Autodesk Fusion 360 part; units mm, degrees
(part 4 of 10)
ref_plane "WorkPlane1" through (0, 0, -5) normal (0, 0, 1) x (1, 0, 0) in component "METAL cap 01"
sketch "Visible cap sketch (2)" plane through (0, 0, -5) normal (0, 0, 1) x (1, 0, 0) in component "METAL cap 01"
  circle A0 centre (12, 120) radius 9
  dimension "d1404" = 12
  dimension "d1405" = 120
  dimension "d1406" = 18
  measures "d1404" horizontal distance of origin A0.centre
  measures "d1405" vertical distance of origin A0.centre
  measures "d1406" diameter of A0
extrude "Visible cap'" add sketch "Visible cap sketch (2)" along normal blind 5 separate body makes body 17 in component "METAL cap 01"
ref_plane "WorkPlane2" through (0, 0, -5) normal (0, 0, 1) x (1, 0, 0) in component "METAL cap 01"
sketch "M5 clearance sketch (2)" plane through (0, 0, -5) normal (0, 0, 1) x (1, 0, 0) in component "METAL cap 01"
  circle A0 centre (12, 120) radius 2.75
  dimension "d1411" = 12
  dimension "d1412" = 120
  dimension "d1413" = 5.5
  measures "d1411" horizontal distance of origin A0.centre
  measures "d1412" vertical distance of origin A0.centre
  measures "d1413" diameter of A0
extrude "M5 clearance'" cut sketch "M5 clearance sketch (2)" along normal blind 5 bodies 17 in component "METAL cap 01"
ref_plane "WorkPlane1" through (0, 0, 5) normal (0, 0, 1) x (1, 0, 0) in component "PRINT registration seat 01"
sketch "Rear bearing seat sketch (2)" plane through (0, 0, 5) normal (0, 0, 1) x (1, 0, 0) in component "PRINT registration seat 01"
  circle A0 centre (12, 120) radius 9
  dimension "d1418" = 12
  dimension "d1419" = 120
  dimension "d1420" = 18
  measures "d1418" horizontal distance of origin A0.centre
  measures "d1419" vertical distance of origin A0.centre
  measures "d1420" diameter of A0
extrude "Rear bearing seat'" add sketch "Rear bearing seat sketch (2)" along normal blind 2 separate body makes body 18 in component "PRINT registration seat 01"
ref_plane "WorkPlane2" through (0, 0, 5) normal (0, 0, 1) x (1, 0, 0) in component "PRINT registration seat 01"
sketch "Shoulder clearance sketch (2)" plane through (0, 0, 5) normal (0, 0, 1) x (1, 0, 0) in component "PRINT registration seat 01"
  circle A0 centre (12, 120) radius 4.2
  dimension "d1425" = 12
  dimension "d1426" = 120
  dimension "d1427" = 8.4
  measures "d1425" horizontal distance of origin A0.centre
  measures "d1426" vertical distance of origin A0.centre
  measures "d1427" diameter of A0
extrude "Shoulder clearance'" cut sketch "Shoulder clearance sketch (2)" along normal blind 2 bodies 18 in component "PRINT registration seat 01"
ref_plane "WorkPlane3" through (0, 0, 5) normal (0, 0, 1) x (1, 0, 0) in component "PRINT registration seat 01"
sketch "Forward registration peg sketch (4)" plane through (0, 0, 5) normal (0, 0, 1) x (1, 0, 0) in component "PRINT registration seat 01"
  circle A0 centre (7, 115) radius 1
  dimension "d1432" = 7
  dimension "d1433" = 115
  dimension "d1434" = 2
  measures "d1432" horizontal distance of origin A0.centre
  measures "d1433" vertical distance of origin A0.centre
  measures "d1434" diameter of A0
extrude "Forward registration peg'" add sketch "Forward registration peg sketch (4)" against normal blind 0.8 bodies 18 in component "PRINT registration seat 01"
ref_plane "WorkPlane4" through (0, 0, 5) normal (0, 0, 1) x (1, 0, 0) in component "PRINT registration seat 01"
sketch "Forward registration peg sketch (1) (2)" plane through (0, 0, 5) normal (0, 0, 1) x (1, 0, 0) in component "PRINT registration seat 01"
  circle A0 centre (7, 125) radius 1
  dimension "d1439" = 7
  dimension "d1440" = 125
  dimension "d1441" = 2
  measures "d1439" horizontal distance of origin A0.centre
  measures "d1440" vertical distance of origin A0.centre
  measures "d1441" diameter of A0
extrude "Forward registration peg (1)'" add sketch "Forward registration peg sketch (1) (2)" against normal blind 0.8 bodies 18 in component "PRINT registration seat 01"
ref_plane "WorkPlane5" through (0, 0, 5) normal (0, 0, 1) x (1, 0, 0) in component "PRINT registration seat 01"
sketch "Forward registration peg sketch (2) (2)" plane through (0, 0, 5) normal (0, 0, 1) x (1, 0, 0) in component "PRINT registration seat 01"
  circle A0 centre (17, 115) radius 1
  dimension "d1446" = 17
  dimension "d1447" = 115
  dimension "d1448" = 2
  measures "d1446" horizontal distance of origin A0.centre
  measures "d1447" vertical distance of origin A0.centre
  measures "d1448" diameter of A0
extrude "Forward registration peg (2)'" add sketch "Forward registration peg sketch (2) (2)" against normal blind 0.8 bodies 18 in component "PRINT registration seat 01"
ref_plane "WorkPlane6" through (0, 0, 5) normal (0, 0, 1) x (1, 0, 0) in component "PRINT registration seat 01"
sketch "Forward registration peg sketch (3) (2)" plane through (0, 0, 5) normal (0, 0, 1) x (1, 0, 0) in component "PRINT registration seat 01"
  circle A0 centre (17, 125) radius 1
  dimension "d1453" = 17
  dimension "d1454" = 125
  dimension "d1455" = 2
  measures "d1453" horizontal distance of origin A0.centre
  measures "d1454" vertical distance of origin A0.centre
  measures "d1455" diameter of A0
extrude "Forward registration peg (3)'" add sketch "Forward registration peg sketch (3) (2)" against normal blind 0.8 bodies 18 in component "PRINT registration seat 01"
sketch "8 mm shoulder sketch (2)" plane through (0, 0, 0) normal (0, 0, 1) x (1, 0, 0) in component "METAL stepped compression spacer 01"
  circle A0 centre (12, 120) radius 4
  dimension "d1458" = 12
  dimension "d1459" = 120
  dimension "d1460" = 8
  measures "d1458" horizontal distance of origin A0.centre
  measures "d1459" vertical distance of origin A0.centre
  measures "d1460" diameter of A0
extrude "8 mm shoulder'" add sketch "8 mm shoulder sketch (2)" along normal blind 7 separate body makes body 19 in component "METAL stepped compression spacer 01"
ref_plane "WorkPlane1" through (0, 0, 7) normal (0, 0, 1) x (1, 0, 0) in component "METAL stepped compression spacer 01"
sketch "12 mm base sketch (2)" plane through (0, 0, 7) normal (0, 0, 1) x (1, 0, 0) in component "METAL stepped compression spacer 01"
  circle A0 centre (12, 120) radius 6
  dimension "d1465" = 12
  dimension "d1466" = 120
  dimension "d1467" = 12
  measures "d1465" horizontal distance of origin A0.centre
  measures "d1466" vertical distance of origin A0.centre
  measures "d1467" diameter of A0
extrude "12 mm base'" add sketch "12 mm base sketch (2)" along normal blind 8 bodies 19 in component "METAL stepped compression spacer 01"
sketch "Through bore sketch (2)" plane through (0, 0, 0) normal (0, 0, 1) x (1, 0, 0) in component "METAL stepped compression spacer 01"
  circle A0 centre (12, 120) radius 2.75
  dimension "d1470" = 12
  dimension "d1471" = 120
  dimension "d1472" = 5.5
  measures "d1470" horizontal distance of origin A0.centre
  measures "d1471" vertical distance of origin A0.centre
  measures "d1472" diameter of A0
extrude "Through bore'" cut sketch "Through bore sketch (2)" along normal blind 15 bodies 19 in component "METAL stepped compression spacer 01"
ref_plane "WorkPlane1" through (0, 0, -8) normal (0, 0, 1) x (1, 0, 0) in component "REFERENCE front M5x25 01"
sketch "Button head envelope sketch (2)" plane through (0, 0, -8) normal (0, 0, 1) x (1, 0, 0) in component "REFERENCE front M5x25 01"
  circle A0 centre (12, 120) radius 4.75
  dimension "d1477" = 12
  dimension "d1478" = 120
  dimension "d1479" = 9.5
  measures "d1477" horizontal distance of origin A0.centre
  measures "d1478" vertical distance of origin A0.centre
  measures "d1479" diameter of A0
extrude "Button head envelope'" add sketch "Button head envelope sketch (2)" along normal blind 3 separate body makes body 20 in component "REFERENCE front M5x25 01"
ref_plane "WorkPlane2" through (0, 0, -5) normal (0, 0, 1) x (1, 0, 0) in component "REFERENCE front M5x25 01"
sketch "Shank envelope sketch (2)" plane through (0, 0, -5) normal (0, 0, 1) x (1, 0, 0) in component "REFERENCE front M5x25 01"
  circle A0 centre (12, 120) radius 2.5
  dimension "d1484" = 12
  dimension "d1485" = 120
  dimension "d1486" = 5
  measures "d1484" horizontal distance of origin A0.centre
  measures "d1485" vertical distance of origin A0.centre
  measures "d1486" diameter of A0
extrude "Shank envelope'" add sketch "Shank envelope sketch (2)" along normal blind 25 bodies 20 in component "REFERENCE front M5x25 01"
ref_plane "WorkPlane1" through (0, 0, 16.5) normal (0, 0, 1) x (1, 0, 0) in component "REFERENCE thin METAL channel nut front 01"
sketch "Thin nut envelope sketch (2)" plane through (0, 0, 16.5) normal (0, 0, 1) x (1, 0, 0) in component "REFERENCE thin METAL channel nut front 01"
  line L0 (7.6, 114) -> (16.4, 114)
  line L1 (16.4, 114) -> (16.4, 126)
  line L2 (16.4, 126) -> (7.6, 126)
  line L3 (7.6, 126) -> (7.6, 114)
  dimension "d1491" = 7.6
  dimension "d1492" = 114
  dimension "d1493" = 8.8
  dimension "d1494" = 12
  constraint horizontal L0
  constraint vertical L1
  constraint horizontal L2
  constraint vertical L3
  measures "d1491" horizontal distance of origin L0.start
  measures "d1492" vertical distance of origin L0.start
  measures "d1493" horizontal distance of L0.start L0.end
  measures "d1494" vertical distance of L0.end L1.end
extrude "Thin nut envelope'" add sketch "Thin nut envelope sketch (2)" along normal blind 2.7 separate body makes body 21 in component "REFERENCE thin METAL channel nut front 01"
ref_plane "WorkPlane2" through (0, 0, 16.5) normal (0, 0, 1) x (1, 0, 0) in component "REFERENCE thin METAL channel nut front 01"
sketch "Thread envelope sketch (2)" plane through (0, 0, 16.5) normal (0, 0, 1) x (1, 0, 0) in component "REFERENCE thin METAL channel nut front 01"
  circle A0 centre (12, 120) radius 2.6
  dimension "d1499" = 12
  dimension "d1500" = 120
  dimension "d1501" = 5.2
  measures "d1499" horizontal distance of origin A0.centre
  measures "d1500" vertical distance of origin A0.centre
  measures "d1501" diameter of A0
extrude "Thread envelope'" cut sketch "Thread envelope sketch (2)" along normal blind 2.7 bodies 21 in component "REFERENCE thin METAL channel nut front 01"
ref_plane "WorkPlane1" through (0, 0, -5) normal (0, 0, 1) x (1, 0, 0) in component "METAL cap 02"
sketch "Visible cap sketch (3)" plane through (0, 0, -5) normal (0, 0, 1) x (1, 0, 0) in component "METAL cap 02"
  circle A0 centre (12, 228) radius 9
  dimension "d1506" = 12
  dimension "d1507" = 228
  dimension "d1508" = 18
  measures "d1506" horizontal distance of origin A0.centre
  measures "d1507" vertical distance of origin A0.centre
  measures "d1508" diameter of A0
extrude "Visible cap''" add sketch "Visible cap sketch (3)" along normal blind 5 separate body makes body 22 in component "METAL cap 02"
ref_plane "WorkPlane2" through (0, 0, -5) normal (0, 0, 1) x (1, 0, 0) in component "METAL cap 02"
sketch "M5 clearance sketch (3)" plane through (0, 0, -5) normal (0, 0, 1) x (1, 0, 0) in component "METAL cap 02"
  circle A0 centre (12, 228) radius 2.75
  dimension "d1513" = 12
  dimension "d1514" = 228
  dimension "d1515" = 5.5
  measures "d1513" horizontal distance of origin A0.centre
  measures "d1514" vertical distance of origin A0.centre
  measures "d1515" diameter of A0
extrude "M5 clearance''" cut sketch "M5 clearance sketch (3)" along normal blind 5 bodies 22 in component "METAL cap 02"
ref_plane "WorkPlane1" through (0, 0, 5) normal (0, 0, 1) x (1, 0, 0) in component "PRINT registration seat 02"
sketch "Rear bearing seat sketch (3)" plane through (0, 0, 5) normal (0, 0, 1) x (1, 0, 0) in component "PRINT registration seat 02"
  circle A0 centre (12, 228) radius 9
  dimension "d1520" = 12
  dimension "d1521" = 228
  dimension "d1522" = 18
  measures "d1520" horizontal distance of origin A0.centre
  measures "d1521" vertical distance of origin A0.centre
  measures "d1522" diameter of A0
extrude "Rear bearing seat''" add sketch "Rear bearing seat sketch (3)" along normal blind 2 separate body makes body 23 in component "PRINT registration seat 02"
ref_plane "WorkPlane2" through (0, 0, 5) normal (0, 0, 1) x (1, 0, 0) in component "PRINT registration seat 02"
sketch "Shoulder clearance sketch (3)" plane through (0, 0, 5) normal (0, 0, 1) x (1, 0, 0) in component "PRINT registration seat 02"
  circle A0 centre (12, 228) radius 4.2
  dimension "d1527" = 12
  dimension "d1528" = 228
  dimension "d1529" = 8.4
  measures "d1527" horizontal distance of origin A0.centre
  measures "d1528" vertical distance of origin A0.centre
  measures "d1529" diameter of A0
extrude "Shoulder clearance''" cut sketch "Shoulder clearance sketch (3)" along normal blind 2 bodies 23 in component "PRINT registration seat 02"
ref_plane "WorkPlane3" through (0, 0, 5) normal (0, 0, 1) x (1, 0, 0) in component "PRINT registration seat 02"
sketch "Forward registration peg sketch (5)" plane through (0, 0, 5) normal (0, 0, 1) x (1, 0, 0) in component "PRINT registration seat 02"
  circle A0 centre (7, 223) radius 1
  dimension "d1534" = 7
  dimension "d1535" = 223
  dimension "d1536" = 2
  measures "d1534" horizontal distance of origin A0.centre
  measures "d1535" vertical distance of origin A0.centre
  measures "d1536" diameter of A0
extrude "Forward registration peg''" add sketch "Forward registration peg sketch (5)" against normal blind 0.8 bodies 23 in component "PRINT registration seat 02"
ref_plane "WorkPlane4" through (0, 0, 5) normal (0, 0, 1) x (1, 0, 0) in component "PRINT registration seat 02"
sketch "Forward registration peg sketch (1) (3)" plane through (0, 0, 5) normal (0, 0, 1) x (1, 0, 0) in component "PRINT registration seat 02"
  circle A0 centre (7, 233) radius 1
  dimension "d1541" = 7
  dimension "d1542" = 233
  dimension "d1543" = 2
  measures "d1541" horizontal distance of origin A0.centre
  measures "d1542" vertical distance of origin A0.centre
  measures "d1543" diameter of A0
extrude "Forward registration peg (1)''" add sketch "Forward registration peg sketch (1) (3)" against normal blind 0.8 bodies 23 in component "PRINT registration seat 02"
ref_plane "WorkPlane5" through (0, 0, 5) normal (0, 0, 1) x (1, 0, 0) in component "PRINT registration seat 02"
sketch "Forward registration peg sketch (2) (3)" plane through (0, 0, 5) normal (0, 0, 1) x (1, 0, 0) in component "PRINT registration seat 02"
  circle A0 centre (17, 223) radius 1
  dimension "d1548" = 17
  dimension "d1549" = 223
  dimension "d1550" = 2
  measures "d1548" horizontal distance of origin A0.centre
  measures "d1549" vertical distance of origin A0.centre
  measures "d1550" diameter of A0
extrude "Forward registration peg (2)''" add sketch "Forward registration peg sketch (2) (3)" against normal blind 0.8 bodies 23 in component "PRINT registration seat 02"
ref_plane "WorkPlane6" through (0, 0, 5) normal (0, 0, 1) x (1, 0, 0) in component "PRINT registration seat 02"
sketch "Forward registration peg sketch (3) (3)" plane through (0, 0, 5) normal (0, 0, 1) x (1, 0, 0) in component "PRINT registration seat 02"
  circle A0 centre (17, 233) radius 1
  dimension "d1555" = 17
  dimension "d1556" = 233
  dimension "d1557" = 2
  measures "d1555" horizontal distance of origin A0.centre
  measures "d1556" vertical distance of origin A0.centre
  measures "d1557" diameter of A0
extrude "Forward registration peg (3)''" add sketch "Forward registration peg sketch (3) (3)" against normal blind 0.8 bodies 23 in component "PRINT registration seat 02"
sketch "8 mm shoulder sketch (3)" plane through (0, 0, 0) normal (0, 0, 1) x (1, 0, 0) in component "METAL stepped compression spacer 02"
  circle A0 centre (12, 228) radius 4
  dimension "d1560" = 12
  dimension "d1561" = 228
  dimension "d1562" = 8
  measures "d1560" horizontal distance of origin A0.centre
  measures "d1561" vertical distance of origin A0.centre
  measures "d1562" diameter of A0
extrude "8 mm shoulder''" add sketch "8 mm shoulder sketch (3)" along normal blind 7 separate body makes body 24 in component "METAL stepped compression spacer 02"
ref_plane "WorkPlane1" through (0, 0, 7) normal (0, 0, 1) x (1, 0, 0) in component "METAL stepped compression spacer 02"
sketch "12 mm base sketch (3)" plane through (0, 0, 7) normal (0, 0, 1) x (1, 0, 0) in component "METAL stepped compression spacer 02"
  circle A0 centre (12, 228) radius 6
  dimension "d1567" = 12
  dimension "d1568" = 228
  dimension "d1569" = 12
  measures "d1567" horizontal distance of origin A0.centre
  measures "d1568" vertical distance of origin A0.centre
  measures "d1569" diameter of A0
extrude "12 mm base''" add sketch "12 mm base sketch (3)" along normal blind 8 bodies 24 in component "METAL stepped compression spacer 02"
sketch "Through bore sketch (3)" plane through (0, 0, 0) normal (0, 0, 1) x (1, 0, 0) in component "METAL stepped compression spacer 02"
  circle A0 centre (12, 228) radius 2.75
  dimension "d1572" = 12
  dimension "d1573" = 228
  dimension "d1574" = 5.5
  measures "d1572" horizontal distance of origin A0.centre
  measures "d1573" vertical distance of origin A0.centre
  measures "d1574" diameter of A0
extrude "Through bore''" cut sketch "Through bore sketch (3)" along normal blind 15 bodies 24 in component "METAL stepped compression spacer 02"
ref_plane "WorkPlane1" through (0, 0, -8) normal (0, 0, 1) x (1, 0, 0) in component "REFERENCE front M5x25 02"
sketch "Button head envelope sketch (3)" plane through (0, 0, -8) normal (0, 0, 1) x (1, 0, 0) in component "REFERENCE front M5x25 02"
  circle A0 centre (12, 228) radius 4.75
  dimension "d1579" = 12
  dimension "d1580" = 228
  dimension "d1581" = 9.5
  measures "d1579" horizontal distance of origin A0.centre
  measures "d1580" vertical distance of origin A0.centre
  measures "d1581" diameter of A0
extrude "Button head envelope''" add sketch "Button head envelope sketch (3)" along normal blind 3 separate body makes body 25 in component "REFERENCE front M5x25 02"
ref_plane "WorkPlane2" through (0, 0, -5) normal (0, 0, 1) x (1, 0, 0) in component "REFERENCE front M5x25 02"
sketch "Shank envelope sketch (3)" plane through (0, 0, -5) normal (0, 0, 1) x (1, 0, 0) in component "REFERENCE front M5x25 02"
  circle A0 centre (12, 228) radius 2.5
  dimension "d1586" = 12
  dimension "d1587" = 228
  dimension "d1588" = 5
  measures "d1586" horizontal distance of origin A0.centre
  measures "d1587" vertical distance of origin A0.centre
  measures "d1588" diameter of A0
extrude "Shank envelope''" add sketch "Shank envelope sketch (3)" along normal blind 25 bodies 25 in component "REFERENCE front M5x25 02"
ref_plane "WorkPlane1" through (0, 0, 16.5) normal (0, 0, 1) x (1, 0, 0) in component "REFERENCE thin METAL channel nut front 02"
sketch "Thin nut envelope sketch (3)" plane through (0, 0, 16.5) normal (0, 0, 1) x (1, 0, 0) in component "REFERENCE thin METAL channel nut front 02"
  line L0 (7.6, 222) -> (16.4, 222)
  line L1 (16.4, 222) -> (16.4, 234)
  line L2 (16.4, 234) -> (7.6, 234)
  line L3 (7.6, 234) -> (7.6, 222)
  dimension "d1593" = 7.6
  dimension "d1594" = 222
  dimension "d1595" = 8.8
  dimension "d1596" = 12
  constraint horizontal L0
  constraint vertical L1
  constraint horizontal L2
  constraint vertical L3
  measures "d1593" horizontal distance of origin L0.start
  measures "d1594" vertical distance of origin L0.start
  measures "d1595" horizontal distance of L0.start L0.end
  measures "d1596" vertical distance of L0.end L1.end
extrude "Thin nut envelope''" add sketch "Thin nut envelope sketch (3)" along normal blind 2.7 separate body makes body 26 in component "REFERENCE thin METAL channel nut front 02"
ref_plane "WorkPlane2" through (0, 0, 16.5) normal (0, 0, 1) x (1, 0, 0) in component "REFERENCE thin METAL channel nut front 02"
sketch "Thread envelope sketch (3)" plane through (0, 0, 16.5) normal (0, 0, 1) x (1, 0, 0) in component "REFERENCE thin METAL channel nut front 02"
  circle A0 centre (12, 228) radius 2.6
  dimension "d1601" = 12
  dimension "d1602" = 228
  dimension "d1603" = 5.2
  measures "d1601" horizontal distance of origin A0.centre
  measures "d1602" vertical distance of origin A0.centre
  measures "d1603" diameter of A0
extrude "Thread envelope''" cut sketch "Thread envelope sketch (3)" along normal blind 2.7 bodies 26 in component "REFERENCE thin METAL channel nut front 02"
ref_plane "WorkPlane1" through (0, 0, -5) normal (0, 0, 1) x (1, 0, 0) in component "METAL cap 10"
sketch "Visible cap sketch (4)" plane through (0, 0, -5) normal (0, 0, 1) x (1, 0, 0) in component "METAL cap 10"
  circle A0 centre (120, 12) radius 9
  dimension "d1608" = 120
  dimension "d1609" = 12
  dimension "d1610" = 18
  measures "d1608" horizontal distance of origin A0.centre
  measures "d1609" vertical distance of origin A0.centre
  measures "d1610" diameter of A0
extrude "Visible cap'''" add sketch "Visible cap sketch (4)" along normal blind 5 separate body makes body 27 in component "METAL cap 10"
ref_plane "WorkPlane2" through (0, 0, -5) normal (0, 0, 1) x (1, 0, 0) in component "METAL cap 10"
sketch "M5 clearance sketch (4)" plane through (0, 0, -5) normal (0, 0, 1) x (1, 0, 0) in component "METAL cap 10"
  circle A0 centre (120, 12) radius 2.75
  dimension "d1615" = 120
  dimension "d1616" = 12
  dimension "d1617" = 5.5
  measures "d1615" horizontal distance of origin A0.centre
  measures "d1616" vertical distance of origin A0.centre
  measures "d1617" diameter of A0
extrude "M5 clearance'''" cut sketch "M5 clearance sketch (4)" along normal blind 5 bodies 27 in component "METAL cap 10"
ref_plane "WorkPlane1" through (0, 0, 5) normal (0, 0, 1) x (1, 0, 0) in component "PRINT registration seat 10"
sketch "Rear bearing seat sketch (4)" plane through (0, 0, 5) normal (0, 0, 1) x (1, 0, 0) in component "PRINT registration seat 10"
  circle A0 centre (120, 12) radius 9
  dimension "d1622" = 120
  dimension "d1623" = 12
  dimension "d1624" = 18
  measures "d1622" horizontal distance of origin A0.centre
  measures "d1623" vertical distance of origin A0.centre
  measures "d1624" diameter of A0
extrude "Rear bearing seat'''" add sketch "Rear bearing seat sketch (4)" along normal blind 2 separate body makes body 28 in component "PRINT registration seat 10"
ref_plane "WorkPlane2" through (0, 0, 5) normal (0, 0, 1) x (1, 0, 0) in component "PRINT registration seat 10"
sketch "Shoulder clearance sketch (4)" plane through (0, 0, 5) normal (0, 0, 1) x (1, 0, 0) in component "PRINT registration seat 10"
  circle A0 centre (120, 12) radius 4.2
  dimension "d1629" = 120
  dimension "d1630" = 12
  dimension "d1631" = 8.4
  measures "d1629" horizontal distance of origin A0.centre
  measures "d1630" vertical distance of origin A0.centre
  measures "d1631" diameter of A0
extrude "Shoulder clearance'''" cut sketch "Shoulder clearance sketch (4)" along normal blind 2 bodies 28 in component "PRINT registration seat 10"
ref_plane "WorkPlane3" through (0, 0, 5) normal (0, 0, 1) x (1, 0, 0) in component "PRINT registration seat 10"
sketch "Forward registration peg sketch (6)" plane through (0, 0, 5) normal (0, 0, 1) x (1, 0, 0) in component "PRINT registration seat 10"
  circle A0 centre (115, 7) radius 1
  dimension "d1636" = 115
  dimension "d1637" = 7
  dimension "d1638" = 2
  measures "d1636" horizontal distance of origin A0.centre
  measures "d1637" vertical distance of origin A0.centre
  measures "d1638" diameter of A0
extrude "Forward registration peg'''" add sketch "Forward registration peg sketch (6)" against normal blind 0.8 bodies 28 in component "PRINT registration seat 10"
ref_plane "WorkPlane4" through (0, 0, 5) normal (0, 0, 1) x (1, 0, 0) in component "PRINT registration seat 10"
sketch "Forward registration peg sketch (1) (4)" plane through (0, 0, 5) normal (0, 0, 1) x (1, 0, 0) in component "PRINT registration seat 10"
  circle A0 centre (115, 17) radius 1
  dimension "d1643" = 115
  dimension "d1644" = 17
  dimension "d1645" = 2
  measures "d1643" horizontal distance of origin A0.centre
  measures "d1644" vertical distance of origin A0.centre
  measures "d1645" diameter of A0
extrude "Forward registration peg (1)'''" add sketch "Forward registration peg sketch (1) (4)" against normal blind 0.8 bodies 28 in component "PRINT registration seat 10"
ref_plane "WorkPlane5" through (0, 0, 5) normal (0, 0, 1) x (1, 0, 0) in component "PRINT registration seat 10"
sketch "Forward registration peg sketch (2) (4)" plane through (0, 0, 5) normal (0, 0, 1) x (1, 0, 0) in component "PRINT registration seat 10"
  circle A0 centre (125, 7) radius 1
  dimension "d1650" = 125
  dimension "d1651" = 7
  dimension "d1652" = 2
  measures "d1650" horizontal distance of origin A0.centre
  measures "d1651" vertical distance of origin A0.centre
  measures "d1652" diameter of A0
extrude "Forward registration peg (2)'''" add sketch "Forward registration peg sketch (2) (4)" against normal blind 0.8 bodies 28 in component "PRINT registration seat 10"
ref_plane "WorkPlane6" through (0, 0, 5) normal (0, 0, 1) x (1, 0, 0) in component "PRINT registration seat 10"
sketch "Forward registration peg sketch (3) (4)" plane through (0, 0, 5) normal (0, 0, 1) x (1, 0, 0) in component "PRINT registration seat 10"
  circle A0 centre (125, 17) radius 1
  dimension "d1657" = 125
  dimension "d1658" = 17
  dimension "d1659" = 2
  measures "d1657" horizontal distance of origin A0.centre
  measures "d1658" vertical distance of origin A0.centre
  measures "d1659" diameter of A0
extrude "Forward registration peg (3)'''" add sketch "Forward registration peg sketch (3) (4)" against normal blind 0.8 bodies 28 in component "PRINT registration seat 10"
sketch "8 mm shoulder sketch (4)" plane through (0, 0, 0) normal (0, 0, 1) x (1, 0, 0) in component "METAL stepped compression spacer 10"
  circle A0 centre (120, 12) radius 4
  dimension "d1662" = 120
  dimension "d1663" = 12
  dimension "d1664" = 8
  measures "d1662" horizontal distance of origin A0.centre
  measures "d1663" vertical distance of origin A0.centre
  measures "d1664" diameter of A0
extrude "8 mm shoulder'''" add sketch "8 mm shoulder sketch (4)" along normal blind 7 separate body makes body 29 in component "METAL stepped compression spacer 10"
ref_plane "WorkPlane1" through (0, 0, 7) normal (0, 0, 1) x (1, 0, 0) in component "METAL stepped compression spacer 10"
sketch "12 mm base sketch (4)" plane through (0, 0, 7) normal (0, 0, 1) x (1, 0, 0) in component "METAL stepped compression spacer 10"
  circle A0 centre (120, 12) radius 6
  dimension "d1669" = 120
  dimension "d1670" = 12
  dimension "d1671" = 12
  measures "d1669" horizontal distance of origin A0.centre
  measures "d1670" vertical distance of origin A0.centre
  measures "d1671" diameter of A0
extrude "12 mm base'''" add sketch "12 mm base sketch (4)" along normal blind 8 bodies 29 in component "METAL stepped compression spacer 10"
sketch "Through bore sketch (4)" plane through (0, 0, 0) normal (0, 0, 1) x (1, 0, 0) in component "METAL stepped compression spacer 10"
  circle A0 centre (120, 12) radius 2.75
  dimension "d1674" = 120
  dimension "d1675" = 12
  dimension "d1676" = 5.5
  measures "d1674" horizontal distance of origin A0.centre
  measures "d1675" vertical distance of origin A0.centre
  measures "d1676" diameter of A0
extrude "Through bore'''" cut sketch "Through bore sketch (4)" along normal blind 15 bodies 29 in component "METAL stepped compression spacer 10"
ref_plane "WorkPlane1" through (0, 0, -8) normal (0, 0, 1) x (1, 0, 0) in component "REFERENCE front M5x25 10"
sketch "Button head envelope sketch (4)" plane through (0, 0, -8) normal (0, 0, 1) x (1, 0, 0) in component "REFERENCE front M5x25 10"
  circle A0 centre (120, 12) radius 4.75
  dimension "d1681" = 120
  dimension "d1682" = 12
  dimension "d1683" = 9.5
  measures "d1681" horizontal distance of origin A0.centre
  measures "d1682" vertical distance of origin A0.centre
  measures "d1683" diameter of A0
extrude "Button head envelope'''" add sketch "Button head envelope sketch (4)" along normal blind 3 separate body makes body 30 in component "REFERENCE front M5x25 10"
ref_plane "WorkPlane2" through (0, 0, -5) normal (0, 0, 1) x (1, 0, 0) in component "REFERENCE front M5x25 10"
sketch "Shank envelope sketch (4)" plane through (0, 0, -5) normal (0, 0, 1) x (1, 0, 0) in component "REFERENCE front M5x25 10"
  circle A0 centre (120, 12) radius 2.5
  dimension "d1688" = 120
  dimension "d1689" = 12
  dimension "d1690" = 5
  measures "d1688" horizontal distance of origin A0.centre
  measures "d1689" vertical distance of origin A0.centre
  measures "d1690" diameter of A0
extrude "Shank envelope'''" add sketch "Shank envelope sketch (4)" along normal blind 25 bodies 30 in component "REFERENCE front M5x25 10"
ref_plane "WorkPlane1" through (0, 0, 16.5) normal (0, 0, 1) x (1, 0, 0) in component "REFERENCE thin METAL channel nut front 10"
sketch "Thin nut envelope sketch (4)" plane through (0, 0, 16.5) normal (0, 0, 1) x (1, 0, 0) in component "REFERENCE thin METAL channel nut front 10"
  line L0 (115.6, 6) -> (124.4, 6)
  line L1 (124.4, 6) -> (124.4, 18)
  line L2 (124.4, 18) -> (115.6, 18)
  line L3 (115.6, 18) -> (115.6, 6)
  dimension "d1695" = 115.6
  dimension "d1696" = 6
  dimension "d1697" = 8.8
  dimension "d1698" = 12
  constraint horizontal L0
  constraint vertical L1
  constraint horizontal L2
  constraint vertical L3
  measures "d1695" horizontal distance of origin L0.start
  measures "d1696" vertical distance of origin L0.start
  measures "d1697" horizontal distance of L0.start L0.end
  measures "d1698" vertical distance of L0.end L1.end
extrude "Thin nut envelope'''" add sketch "Thin nut envelope sketch (4)" along normal blind 2.7 separate body makes body 31 in component "REFERENCE thin METAL channel nut front 10"
ref_plane "WorkPlane2" through (0, 0, 16.5) normal (0, 0, 1) x (1, 0, 0) in component "REFERENCE thin METAL channel nut front 10"
sketch "Thread envelope sketch (4)" plane through (0, 0, 16.5) normal (0, 0, 1) x (1, 0, 0) in component "REFERENCE thin METAL channel nut front 10"
  circle A0 centre (120, 12) radius 2.6
  dimension "d1703" = 120
  dimension "d1704" = 12
  dimension "d1705" = 5.2
  measures "d1703" horizontal distance of origin A0.centre
  measures "d1704" vertical distance of origin A0.centre
  measures "d1705" diameter of A0
extrude "Thread envelope'''" cut sketch "Thread envelope sketch (4)" along normal blind 2.7 bodies 31 in component "REFERENCE thin METAL channel nut front 10"
ref_plane "WorkPlane1" through (0, 0, -5) normal (0, 0, 1) x (1, 0, 0) in component "METAL cap 11"
sketch "Visible cap sketch (5)" plane through (0, 0, -5) normal (0, 0, 1) x (1, 0, 0) in component "METAL cap 11"
  circle A0 centre (120, 120) radius 9
  dimension "d1710" = 120
  dimension "d1711" = 120
  dimension "d1712" = 18
  measures "d1710" horizontal distance of origin A0.centre
  measures "d1711" vertical distance of origin A0.centre
  measures "d1712" diameter of A0
extrude "Visible cap''''" add sketch "Visible cap sketch (5)" along normal blind 5 separate body makes body 32 in component "METAL cap 11"
ref_plane "WorkPlane2" through (0, 0, -5) normal (0, 0, 1) x (1, 0, 0) in component "METAL cap 11"
sketch "M5 clearance sketch (5)" plane through (0, 0, -5) normal (0, 0, 1) x (1, 0, 0) in component "METAL cap 11"
  circle A0 centre (120, 120) radius 2.75
  dimension "d1717" = 120
  dimension "d1718" = 120
  dimension "d1719" = 5.5
  measures "d1717" horizontal distance of origin A0.centre
  measures "d1718" vertical distance of origin A0.centre
  measures "d1719" diameter of A0
extrude "M5 clearance''''" cut sketch "M5 clearance sketch (5)" along normal blind 5 bodies 32 in component "METAL cap 11"
ref_plane "WorkPlane1" through (0, 0, 5) normal (0, 0, 1) x (1, 0, 0) in component "PRINT registration seat 11"
sketch "Rear bearing seat sketch (5)" plane through (0, 0, 5) normal (0, 0, 1) x (1, 0, 0) in component "PRINT registration seat 11"
  circle A0 centre (120, 120) radius 9
  dimension "d1724" = 120
  dimension "d1725" = 120
  dimension "d1726" = 18
  measures "d1724" horizontal distance of origin A0.centre
  measures "d1725" vertical distance of origin A0.centre
  measures "d1726" diameter of A0
extrude "Rear bearing seat''''" add sketch "Rear bearing seat sketch (5)" along normal blind 2 separate body makes body 33 in component "PRINT registration seat 11"
ref_plane "WorkPlane2" through (0, 0, 5) normal (0, 0, 1) x (1, 0, 0) in component "PRINT registration seat 11"
sketch "Shoulder clearance sketch (5)" plane through (0, 0, 5) normal (0, 0, 1) x (1, 0, 0) in component "PRINT registration seat 11"
  circle A0 centre (120, 120) radius 4.2
  dimension "d1731" = 120
  dimension "d1732" = 120
  dimension "d1733" = 8.4
  measures "d1731" horizontal distance of origin A0.centre
  measures "d1732" vertical distance of origin A0.centre
  measures "d1733" diameter of A0
extrude "Shoulder clearance''''" cut sketch "Shoulder clearance sketch (5)" along normal blind 2 bodies 33 in component "PRINT registration seat 11"
ref_plane "WorkPlane3" through (0, 0, 5) normal (0, 0, 1) x (1, 0, 0) in component "PRINT registration seat 11"
sketch "Forward registration peg sketch (7)" plane through (0, 0, 5) normal (0, 0, 1) x (1, 0, 0) in component "PRINT registration seat 11"
  circle A0 centre (115, 115) radius 1
  dimension "d1738" = 115
  dimension "d1739" = 115
  dimension "d1740" = 2
  measures "d1738" horizontal distance of origin A0.centre
  measures "d1739" vertical distance of origin A0.centre
  measures "d1740" diameter of A0
extrude "Forward registration peg''''" add sketch "Forward registration peg sketch (7)" against normal blind 0.8 bodies 33 in component "PRINT registration seat 11"
ref_plane "WorkPlane4" through (0, 0, 5) normal (0, 0, 1) x (1, 0, 0) in component "PRINT registration seat 11"
sketch "Forward registration peg sketch (1) (5)" plane through (0, 0, 5) normal (0, 0, 1) x (1, 0, 0) in component "PRINT registration seat 11"
  circle A0 centre (115, 125) radius 1
  dimension "d1745" = 115
  dimension "d1746" = 125
  dimension "d1747" = 2
  measures "d1745" horizontal distance of origin A0.centre
  measures "d1746" vertical distance of origin A0.centre
  measures "d1747" diameter of A0
extrude "Forward registration peg (1)''''" add sketch "Forward registration peg sketch (1) (5)" against normal blind 0.8 bodies 33 in component "PRINT registration seat 11"
ref_plane "WorkPlane5" through (0, 0, 5) normal (0, 0, 1) x (1, 0, 0) in component "PRINT registration seat 11"
sketch "Forward registration peg sketch (2) (5)" plane through (0, 0, 5) normal (0, 0, 1) x (1, 0, 0) in component "PRINT registration seat 11"
  circle A0 centre (125, 115) radius 1
  dimension "d1752" = 125
  dimension "d1753" = 115
  dimension "d1754" = 2
  measures "d1752" horizontal distance of origin A0.centre
  measures "d1753" vertical distance of origin A0.centre
  measures "d1754" diameter of A0
extrude "Forward registration peg (2)''''" add sketch "Forward registration peg sketch (2) (5)" against normal blind 0.8 bodies 33 in component "PRINT registration seat 11"
ref_plane "WorkPlane6" through (0, 0, 5) normal (0, 0, 1) x (1, 0, 0) in component "PRINT registration seat 11"
sketch "Forward registration peg sketch (3) (5)" plane through (0, 0, 5) normal (0, 0, 1) x (1, 0, 0) in component "PRINT registration seat 11"
  circle A0 centre (125, 125) radius 1
  dimension "d1759" = 125
  dimension "d1760" = 125
  dimension "d1761" = 2
  measures "d1759" horizontal distance of origin A0.centre
  measures "d1760" vertical distance of origin A0.centre
  measures "d1761" diameter of A0
extrude "Forward registration peg (3)''''" add sketch "Forward registration peg sketch (3) (5)" against normal blind 0.8 bodies 33 in component "PRINT registration seat 11"
sketch "8 mm shoulder sketch (5)" plane through (0, 0, 0) normal (0, 0, 1) x (1, 0, 0) in component "METAL stepped compression spacer 11"
  circle A0 centre (120, 120) radius 4
  dimension "d1764" = 120
  dimension "d1765" = 120
  dimension "d1766" = 8
  measures "d1764" horizontal distance of origin A0.centre
  measures "d1765" vertical distance of origin A0.centre
  measures "d1766" diameter of A0
extrude "8 mm shoulder''''" add sketch "8 mm shoulder sketch (5)" along normal blind 7 separate body makes body 34 in component "METAL stepped compression spacer 11"
ref_plane "WorkPlane1" through (0, 0, 7) normal (0, 0, 1) x (1, 0, 0) in component "METAL stepped compression spacer 11"
sketch "12 mm base sketch (5)" plane through (0, 0, 7) normal (0, 0, 1) x (1, 0, 0) in component "METAL stepped compression spacer 11"
  circle A0 centre (120, 120) radius 6
  dimension "d1771" = 120
  dimension "d1772" = 120
  dimension "d1773" = 12
  measures "d1771" horizontal distance of origin A0.centre
  measures "d1772" vertical distance of origin A0.centre
  measures "d1773" diameter of A0
extrude "12 mm base''''" add sketch "12 mm base sketch (5)" along normal blind 8 bodies 34 in component "METAL stepped compression spacer 11"
sketch "Through bore sketch (5)" plane through (0, 0, 0) normal (0, 0, 1) x (1, 0, 0) in component "METAL stepped compression spacer 11"
  circle A0 centre (120, 120) radius 2.75
  dimension "d1776" = 120
  dimension "d1777" = 120
  dimension "d1778" = 5.5
  measures "d1776" horizontal distance of origin A0.centre
  measures "d1777" vertical distance of origin A0.centre
  measures "d1778" diameter of A0
extrude "Through bore''''" cut sketch "Through bore sketch (5)" along normal blind 15 bodies 34 in component "METAL stepped compression spacer 11"
ref_plane "WorkPlane1" through (0, 0, -8) normal (0, 0, 1) x (1, 0, 0) in component "REFERENCE front M5x25 11"
sketch "Button head envelope sketch (5)" plane through (0, 0, -8) normal (0, 0, 1) x (1, 0, 0) in component "REFERENCE front M5x25 11"
  circle A0 centre (120, 120) radius 4.75
  dimension "d1783" = 120
  dimension "d1784" = 120
  dimension "d1785" = 9.5
  measures "d1783" horizontal distance of origin A0.centre
  measures "d1784" vertical distance of origin A0.centre
  measures "d1785" diameter of A0
extrude "Button head envelope''''" add sketch "Button head envelope sketch (5)" along normal blind 3 separate body makes body 35 in component "REFERENCE front M5x25 11"
ref_plane "WorkPlane2" through (0, 0, -5) normal (0, 0, 1) x (1, 0, 0) in component "REFERENCE front M5x25 11"
sketch "Shank envelope sketch (5)" plane through (0, 0, -5) normal (0, 0, 1) x (1, 0, 0) in component "REFERENCE front M5x25 11"
  circle A0 centre (120, 120) radius 2.5
  dimension "d1790" = 120
  dimension "d1791" = 120
  dimension "d1792" = 5
  measures "d1790" horizontal distance of origin A0.centre
  measures "d1791" vertical distance of origin A0.centre
  measures "d1792" diameter of A0
extrude "Shank envelope''''" add sketch "Shank envelope sketch (5)" along normal blind 25 bodies 35 in component "REFERENCE front M5x25 11"
ref_plane "WorkPlane1" through (0, 0, 16.5) normal (0, 0, 1) x (1, 0, 0) in component "REFERENCE thin METAL channel nut front 11"
sketch "Thin nut envelope sketch (5)" plane through (0, 0, 16.5) normal (0, 0, 1) x (1, 0, 0) in component "REFERENCE thin METAL channel nut front 11"
  line L0 (115.6, 114) -> (124.4, 114)
  line L1 (124.4, 114) -> (124.4, 126)
  line L2 (124.4, 126) -> (115.6, 126)
  line L3 (115.6, 126) -> (115.6, 114)
  dimension "d1797" = 115.6
  dimension "d1798" = 114
  dimension "d1799" = 8.8
  dimension "d1800" = 12
  constraint horizontal L0
  constraint vertical L1
  constraint horizontal L2
  constraint vertical L3
  measures "d1797" horizontal distance of origin L0.start
  measures "d1798" vertical distance of origin L0.start
  measures "d1799" horizontal distance of L0.start L0.end
  measures "d1800" vertical distance of L0.end L1.end
extrude "Thin nut envelope''''" add sketch "Thin nut envelope sketch (5)" along normal blind 2.7 separate body makes body 36 in component "REFERENCE thin METAL channel nut front 11"
ref_plane "WorkPlane2" through (0, 0, 16.5) normal (0, 0, 1) x (1, 0, 0) in component "REFERENCE thin METAL channel nut front 11"
sketch "Thread envelope sketch (5)" plane through (0, 0, 16.5) normal (0, 0, 1) x (1, 0, 0) in component "REFERENCE thin METAL channel nut front 11"
  circle A0 centre (120, 120) radius 2.6
  dimension "d1805" = 120
  dimension "d1806" = 120
  dimension "d1807" = 5.2
  measures "d1805" horizontal distance of origin A0.centre
  measures "d1806" vertical distance of origin A0.centre
  measures "d1807" diameter of A0
extrude "Thread envelope''''" cut sketch "Thread envelope sketch (5)" along normal blind 2.7 bodies 36 in component "REFERENCE thin METAL channel nut front 11"
ref_plane "WorkPlane1" through (0, 0, -5) normal (0, 0, 1) x (1, 0, 0) in component "METAL cap 12"
sketch "Visible cap sketch (6)" plane through (0, 0, -5) normal (0, 0, 1) x (1, 0, 0) in component "METAL cap 12"
  circle A0 centre (120, 228) radius 9
  dimension "d1812" = 120
  dimension "d1813" = 228
  dimension "d1814" = 18
  measures "d1812" horizontal distance of origin A0.centre
  measures "d1813" vertical distance of origin A0.centre
  measures "d1814" diameter of A0
extrude "Visible cap'''''" add sketch "Visible cap sketch (6)" along normal blind 5 separate body makes body 37 in component "METAL cap 12"
ref_plane "WorkPlane2" through (0, 0, -5) normal (0, 0, 1) x (1, 0, 0) in component "METAL cap 12"
sketch "M5 clearance sketch (6)" plane through (0, 0, -5) normal (0, 0, 1) x (1, 0, 0) in component "METAL cap 12"
  circle A0 centre (120, 228) radius 2.75
  dimension "d1819" = 120
  dimension "d1820" = 228
  dimension "d1821" = 5.5
  measures "d1819" horizontal distance of origin A0.centre
  measures "d1820" vertical distance of origin A0.centre
  measures "d1821" diameter of A0
extrude "M5 clearance'''''" cut sketch "M5 clearance sketch (6)" along normal blind 5 bodies 37 in component "METAL cap 12"
ref_plane "WorkPlane1" through (0, 0, 5) normal (0, 0, 1) x (1, 0, 0) in component "PRINT registration seat 12"
sketch "Rear bearing seat sketch (6)" plane through (0, 0, 5) normal (0, 0, 1) x (1, 0, 0) in component "PRINT registration seat 12"
  circle A0 centre (120, 228) radius 9
  dimension "d1826" = 120
  dimension "d1827" = 228
  dimension "d1828" = 18
  measures "d1826" horizontal distance of origin A0.centre
  measures "d1827" vertical distance of origin A0.centre
  measures "d1828" diameter of A0
extrude "Rear bearing seat'''''" add sketch "Rear bearing seat sketch (6)" along normal blind 2 separate body makes body 38 in component "PRINT registration seat 12"
ref_plane "WorkPlane2" through (0, 0, 5) normal (0, 0, 1) x (1, 0, 0) in component "PRINT registration seat 12"
sketch "Shoulder clearance sketch (6)" plane through (0, 0, 5) normal (0, 0, 1) x (1, 0, 0) in component "PRINT registration seat 12"
  circle A0 centre (120, 228) radius 4.2
  dimension "d1833" = 120
  dimension "d1834" = 228
  dimension "d1835" = 8.4
  measures "d1833" horizontal distance of origin A0.centre
  measures "d1834" vertical distance of origin A0.centre
  measures "d1835" diameter of A0
extrude "Shoulder clearance'''''" cut sketch "Shoulder clearance sketch (6)" along normal blind 2 bodies 38 in component "PRINT registration seat 12"
ref_plane "WorkPlane3" through (0, 0, 5) normal (0, 0, 1) x (1, 0, 0) in component "PRINT registration seat 12"
sketch "Forward registration peg sketch (8)" plane through (0, 0, 5) normal (0, 0, 1) x (1, 0, 0) in component "PRINT registration seat 12"
  circle A0 centre (115, 223) radius 1
  dimension "d1840" = 115
  dimension "d1841" = 223
  dimension "d1842" = 2
  measures "d1840" horizontal distance of origin A0.centre
  measures "d1841" vertical distance of origin A0.centre
  measures "d1842" diameter of A0
extrude "Forward registration peg'''''" add sketch "Forward registration peg sketch (8)" against normal blind 0.8 bodies 38 in component "PRINT registration seat 12"
ref_plane "WorkPlane4" through (0, 0, 5) normal (0, 0, 1) x (1, 0, 0) in component "PRINT registration seat 12"
sketch "Forward registration peg sketch (1) (6)" plane through (0, 0, 5) normal (0, 0, 1) x (1, 0, 0) in component "PRINT registration seat 12"
  circle A0 centre (115, 233) radius 1
  dimension "d1847" = 115
  dimension "d1848" = 233
  dimension "d1849" = 2
  measures "d1847" horizontal distance of origin A0.centre
  measures "d1848" vertical distance of origin A0.centre
  measures "d1849" diameter of A0
extrude "Forward registration peg (1)'''''" add sketch "Forward registration peg sketch (1) (6)" against normal blind 0.8 bodies 38 in component "PRINT registration seat 12"
ref_plane "WorkPlane5" through (0, 0, 5) normal (0, 0, 1) x (1, 0, 0) in component "PRINT registration seat 12"
sketch "Forward registration peg sketch (2) (6)" plane through (0, 0, 5) normal (0, 0, 1) x (1, 0, 0) in component "PRINT registration seat 12"
  circle A0 centre (125, 223) radius 1
  dimension "d1854" = 125
  dimension "d1855" = 223
  dimension "d1856" = 2
  measures "d1854" horizontal distance of origin A0.centre
  measures "d1855" vertical distance of origin A0.centre
  measures "d1856" diameter of A0
extrude "Forward registration peg (2)'''''" add sketch "Forward registration peg sketch (2) (6)" against normal blind 0.8 bodies 38 in component "PRINT registration seat 12"
ref_plane "WorkPlane6" through (0, 0, 5) normal (0, 0, 1) x (1, 0, 0) in component "PRINT registration seat 12"
sketch "Forward registration peg sketch (3) (6)" plane through (0, 0, 5) normal (0, 0, 1) x (1, 0, 0) in component "PRINT registration seat 12"
  circle A0 centre (125, 233) radius 1
  dimension "d1861" = 125
  dimension "d1862" = 233
  dimension "d1863" = 2
  measures "d1861" horizontal distance of origin A0.centre
  measures "d1862" vertical distance of origin A0.centre
  measures "d1863" diameter of A0
extrude "Forward registration peg (3)'''''" add sketch "Forward registration peg sketch (3) (6)" against normal blind 0.8 bodies 38 in component "PRINT registration seat 12"
sketch "8 mm shoulder sketch (6)" plane through (0, 0, 0) normal (0, 0, 1) x (1, 0, 0) in component "METAL stepped compression spacer 12"
  circle A0 centre (120, 228) radius 4
  dimension "d1866" = 120
  dimension "d1867" = 228
  dimension "d1868" = 8
  measures "d1866" horizontal distance of origin A0.centre
  measures "d1867" vertical distance of origin A0.centre
  measures "d1868" diameter of A0
extrude "8 mm shoulder'''''" add sketch "8 mm shoulder sketch (6)" along normal blind 7 separate body makes body 39 in component "METAL stepped compression spacer 12"
ref_plane "WorkPlane1" through (0, 0, 7) normal (0, 0, 1) x (1, 0, 0) in component "METAL stepped compression spacer 12"
sketch "12 mm base sketch (6)" plane through (0, 0, 7) normal (0, 0, 1) x (1, 0, 0) in component "METAL stepped compression spacer 12"
  circle A0 centre (120, 228) radius 6
  dimension "d1873" = 120
  dimension "d1874" = 228
  dimension "d1875" = 12
  measures "d1873" horizontal distance of origin A0.centre
  measures "d1874" vertical distance of origin A0.centre
  measures "d1875" diameter of A0
extrude "12 mm base'''''" add sketch "12 mm base sketch (6)" along normal blind 8 bodies 39 in component "METAL stepped compression spacer 12"
sketch "Through bore sketch (6)" plane through (0, 0, 0) normal (0, 0, 1) x (1, 0, 0) in component "METAL stepped compression spacer 12"
  circle A0 centre (120, 228) radius 2.75
  dimension "d1878" = 120
  dimension "d1879" = 228
  dimension "d1880" = 5.5
  measures "d1878" horizontal distance of origin A0.centre
  measures "d1879" vertical distance of origin A0.centre
  measures "d1880" diameter of A0
extrude "Through bore'''''" cut sketch "Through bore sketch (6)" along normal blind 15 bodies 39 in component "METAL stepped compression spacer 12"
ref_plane "WorkPlane1" through (0, 0, -8) normal (0, 0, 1) x (1, 0, 0) in component "REFERENCE front M5x25 12"
sketch "Button head envelope sketch (6)" plane through (0, 0, -8) normal (0, 0, 1) x (1, 0, 0) in component "REFERENCE front M5x25 12"
  circle A0 centre (120, 228) radius 4.75
  dimension "d1885" = 120
  dimension "d1886" = 228
  dimension "d1887" = 9.5
  measures "d1885" horizontal distance of origin A0.centre
  measures "d1886" vertical distance of origin A0.centre
  measures "d1887" diameter of A0
extrude "Button head envelope'''''" add sketch "Button head envelope sketch (6)" along normal blind 3 separate body makes body 40 in component "REFERENCE front M5x25 12"
ref_plane "WorkPlane2" through (0, 0, -5) normal (0, 0, 1) x (1, 0, 0) in component "REFERENCE front M5x25 12"
sketch "Shank envelope sketch (6)" plane through (0, 0, -5) normal (0, 0, 1) x (1, 0, 0) in component "REFERENCE front M5x25 12"
  circle A0 centre (120, 228) radius 2.5
  dimension "d1892" = 120
  dimension "d1893" = 228
  dimension "d1894" = 5
  measures "d1892" horizontal distance of origin A0.centre
  measures "d1893" vertical distance of origin A0.centre
  measures "d1894" diameter of A0
extrude "Shank envelope'''''" add sketch "Shank envelope sketch (6)" along normal blind 25 bodies 40 in component "REFERENCE front M5x25 12"
ref_plane "WorkPlane1" through (0, 0, 16.5) normal (0, 0, 1) x (1, 0, 0) in component "REFERENCE thin METAL channel nut front 12"